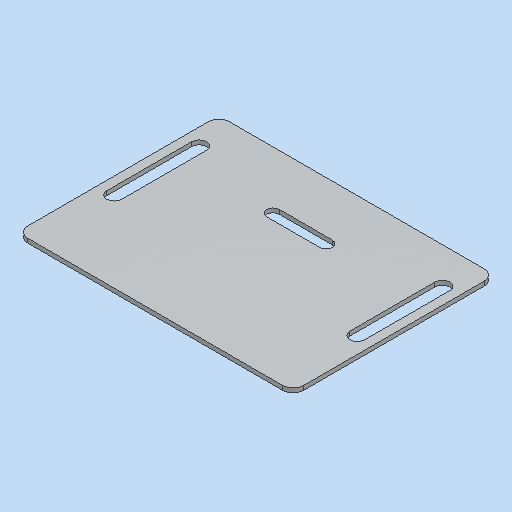
# Autodesk Inventor part: MM0861AN200_G24_107
Saved by Autodesk Inventor 2023.3 (Build 273359000, 359)
## iProperties
RuleStatus: InUse
Part Number: MM0861AN200_G24_107
Material: 3.3535 AlMg3 - AW 5754 (Blech)
Description: =<RBPARTNOTITLE2>
Document SubType Name: Blech
Designer: Benutzer
Mass: 62.1488 g
Surface Area: 244.551 cm^2
Volume: 23.0266 cm^3
Density: 2.699 g/cm^3
Sheet Metal Rule: Standard_mm
Appearance: Aluminium AnP
RBCHANGEDESCRIPTION1: Erstfreigabe
RBCHANGENO1: 00
RBDOCUMENTTYPE: DRF
RBDOCUMENTVERSION: 00
RBDRAWINGMAINSCALE: 1:1
RBDRAWINGMISSINGSPEC: --
RBDRAWINGVOLUME: --
RBDSV1: 0850
RBGBDETAILS: 43274
RBGBEDGESIN1: +0,5
RBGBEDGESIN2: +0,2
RBGBEDGESOUT1: -0,3
RBGBEDGESOUT2: -0,1
RBMATERIAL: =<Material>
RBMATMEETS: --
RBMATNO: =<Part Number>
RBORGUNITRESPONSIBLE1: AnP/TEF1
RBPARTMADEOF: 2 x 95 x 130 (FM)
RBPARTNO: SIEHE MNR
RBPARTNOTITLE1: manufactured part
RBPARTNOTITLE2: Anfertigungsteil
RBPARTSAFETYINDICATOR: --
RBSURFACE: anodised E6/EV1 colourless
RBSURFACE2: eloxiert E6/EV1 aluminiumfarbig
RBZEDGESNORM: ISO13715:2002-06
RBZGENDIMCLASS: m
RBZGENDIMNORM: ISO 2768-1:1989-11
RBZGENGEOCLASS: H
RBZGENGEONORM: ISO 2768-2:1989-11
RBZSURFACENORM: ISO13D2:2002-02
RBZTOLERANCENORM: ISO 14405-1:2010-12
AnP_Material: =<Material>
AnP_TemplVers: 20190222
AnP_Kategorie: 1
MaxAbmaße: 2 x 95 x 130 (FM)
Author: Benutzer
Keywords: =<RBPARTMADEOF>
Comments: =<RBSURFACE2>
Revision Number: 01
Autodesk Inventor part; units mm, degrees
ref_plane "YZ Plane" through (0, 0, 0) normal (1, 0, 0) x (0, 1, 0)
ref_plane "XZ Plane" through (0, 0, 0) normal (0, 1, 0) x (-1, 0, 0)
ref_plane "XY Plane" through (0, 0, 0) normal (0, 0, 1) x (1, 0, 0)
sketch "Skizze1" plane through (0, 0, 0) normal (0, 0, 1) x (1, 0, 0)
  line L0 (0, 0) -> (130, 0)
  line L1 (130, 0) -> (130, 80)
  line L2 (130, 80) -> (0, 80)
  line L3 (0, 80) -> (0, 0)
  dimension "d0" = 130
  dimension "d1" = 80
  measures "d0" distance of L2.end L1.end
  measures "d1" distance of L1.end L0.end
extrude "Grobblech1" add sketch "Skizze1" along normal blind 2
sketch "Skizze2" plane through (0, 0, 2) normal (0, 0, 1) x (1, 0, 0)
  line L0 (130, 0) -> (0, 0) projected
  line L1 (0, 0) -> (0, 80) projected
  point P0 (7.75, 43)
  point P1 (122.25, 43)
  dimension "d3" = 114.5
  dimension "d4" = 43
  dimension "d5" = 7.75
  constraints: 1 horizontal alignment
  measures "d3" distance of point (122.25, 43) point (7.75, 43)
  measures "d4" distance from line of point (7.75, 43) L0
  measures "d5" distance from line of point (7.75, 43) L1
hole "Bohrung1" at (7.75, 43, 2) at (122.25, 43, 2) direction (0, 0, -1) diameter 6.5 depth 2 tip angle 118
sketch "Skizze3" plane through (0, 0, 2) normal (0, 0, 1) x (1, 0, 0)
  line L0 (7.75, 63) -> (7.75, 23) construction
  line L1 (4.25, 63) -> (4.25, 23)
  line L2 (11.25, 23) -> (11.25, 63)
  arc A0 (11.25, 63) -> (4.25, 63) centre (7.75, 63) ccw
  arc A1 (4.25, 23) -> (11.25, 23) centre (7.75, 23) ccw
  circle A2 centre (7.75, 43) radius 3.25 projected
  line L3 (122.25, 63) -> (122.25, 23) construction
  line L4 (118.75, 63) -> (118.75, 23)
  line L5 (125.75, 23) -> (125.75, 63)
  arc A3 (125.75, 63) -> (118.75, 63) centre (122.25, 63) ccw
  arc A4 (118.75, 23) -> (125.75, 23) centre (122.25, 23) ccw
  circle A5 centre (122.25, 43) radius 3.25 projected
  point P0 (0, 0)
  dimension "d13" = 40
  dimension "d14" = 7
  dimension "d15" = 7
  constraints: 16 end point, 8 point on circle, 8 tangent, 4 centre point, 3 coincident, 2 horizontal alignment, 2 midpoint, 2 parallel, 2 vertical
  measures "d13" distance of L0.start L0.end
  measures "d14" diameter of A1
  measures "d15" diameter of A4
extrude "Extrusion1" cut sketch "Skizze3" against normal blind 10
sketch "Skizze4" plane through (0, 0, 2) normal (0, 0, 1) x (1, 0, 0)
  line L0 (52.5, 53) -> (77.5, 53) construction
  line L1 (52.5, 50) -> (77.5, 50)
  line L2 (77.5, 56) -> (52.5, 56)
  arc A0 (52.5, 56) -> (52.5, 50) centre (52.5, 53) ccw
  arc A1 (77.5, 50) -> (77.5, 56) centre (77.5, 53) ccw
  arc A2 (4.25, 23) -> (11.25, 23) centre (7.75, 23) ccw projected
  line L3 (4.25, 23) -> (4.25, 63) projected
  arc A3 (11.25, 63) -> (4.25, 63) centre (7.75, 63) ccw projected
  line L4 (11.25, 63) -> (11.25, 23) projected
  arc A4 (118.75, 23) -> (125.75, 23) centre (122.25, 23) ccw projected
  line L5 (118.75, 23) -> (118.75, 63) projected
  arc A5 (125.75, 63) -> (118.75, 63) centre (122.25, 63) ccw projected
  line L6 (125.75, 63) -> (125.75, 23) projected
  line L7 (0, 0) -> (0, 80) projected
  line L8 (130, 0) -> (0, 0) projected
  line L9 (130, 80) -> (130, 0) projected
  line L10 (0, 80) -> (130, 80) projected
  point P0 (65, 53)
  dimension "d18" = 6
  dimension "d19" = 25
  dimension "d20" = 40
  dimension "d21" = 30
  dimension "d22" = 114.5
  dimension "d23" = 57.25
  constraints: 8 end point, 4 point on circle, 4 tangent, 2 centre point, 1 horizontal, 1 midpoint, 1 parallel
  measures "d18" diameter of A1
  measures "d19" distance of L0.end L0.start
  measures "d20" distance of A2.centre A3.centre
  measures "d21" vertical distance of A2.centre point (65, 53)
  measures "d22" distance of A4.centre A2.centre
  measures "d23" horizontal distance of point (65, 53) A2.centre
extrude "Extrusion2" cut sketch "Skizze4" against normal blind 10 contours A0 L2 A1 L1
sketch "Skizze5" plane through (0, 0, 0) normal (0, -1, 0) x (1, 0, 0)
  line L0 (130, 2) -> (0, 2) projected
  line L1 (0, 0) -> (0, 2) projected
  line L2 (0, 0) -> (130, 0) projected
  line L3 (130, 0) -> (130, 2) projected
extrude "Extrusion3" add sketch "Skizze5" along normal blind 15
fillet "Rundung1" radius 5 4 edges at (130, -15, 1) (0, -15, 1) (0, 80, 1) (130, 80, 1)
equation "\"d11\" = Stärke"
equation "\"d29\" = Stärke"
equation "\"d23\" = 0.5 * d22"
equation "\"Biegeradius\" = Stärke"
equation "\"BreiteBiegungsfreistellung\" = Stärke"
equation "\"TiefeBiegungsfreistellung\" = 0.5 * Stärke"
equation "\"GrößeEckenfreistellung\" = 4 * Stärke"
equation "\"MinimalRest\" = 2 * Stärke"
equation "\"Übergangsradius\" = Biegeradius"
equation "\"JacobiRadiusGröße\" = Biegeradius"
equation "\"Abstandsgröße\" = Stärke"
equation "\"d2\" = Biegeradius"
equation "\"Stärke\" = 2"
